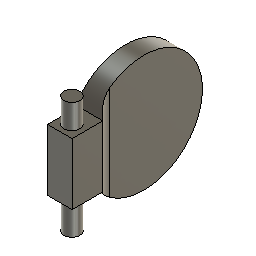
assembly engine1 (Autodesk Fusion 360 archive; units mm, degrees)
design "closing element"
part number: 2026-03-27-16-31-58-847
Autodesk Fusion 360 part; units mm, degrees
sketch "Sketch1" plane through (0, 0, 0) normal (1, 0, 0) x (0, 1, 0)
  circle A0 centre (0, 0) radius 9.5
  dimension "d1" = 19
  constraint coincident A0.centre origin
  measures "d1" diameter of A0
extrude "Extrude1" add sketch "Sketch1" along normal blind 3
sketch "Sketch2" plane through (3, 0, 0) normal (1, 0, 0) x (0, 1, 0)
  circle A0 centre (0, 0) radius 9.5
  line L0 (-8.0777, 5) -> (-13.0777, 5)
  line L1 (-13.0777, 5) -> (-13.0777, -5)
  line L2 (-13.0777, -5) -> (-8.0777, -5)
  line L3 (-8.0777, -5) -> (-8.0777, 5)
  dimension "d4" = 5
  dimension "d5" = 10
  constraint horizontal L0
  constraint vertical L1
  constraint horizontal L2
  constraint vertical L3
  constraint coincident A0 L0.start
  constraint coincident A0 L2.end
  measures "d4" distance of L0.start L0.end
  measures "d5" distance of L0.start L2.end
extrude "Extrude2" add sketch "Sketch2" along normal blind 1 contours A0 L3 | A0 L0 L1 L2 picked at (-8.2821, 1.2788)
extrude "Extrude3" add 1 faces at (3, -11.8852, 0) along direction (-1, 0, 0) blind 2.6
extrude "Extrude4" add 1 faces at (4, -11.4111, 1.6667) along direction (1, 0, 0) blind 0.4
sketch "Sketch3" plane through (0, 0, -5) normal (0, 0, -1) x (1, 0, 0)
  line L0 (3, 8.0777) -> (4.4, 8.0777)
  line L1 (4.4, 8.0777) -> (4.4, 13.0777)
  line L2 (4.4, 13.0777) -> (0.4, 13.0777)
  line L3 (0.4, 13.0777) -> (0.4, 8.0777)
  line L4 (0.4, 8.0777) -> (3, 8.0777)
  line L5 (4.4, 13.0777) -> (0.4, 13.0777)
  line L6 (0.4, 13.0777) -> (0.4, 8.0777)
  line L7 (0.4, 8.0777) -> (4.4, 8.0777)
  line L8 (4.4, 8.0777) -> (4.4, 13.0777)
  circle A0 centre (2.36, 11.0777) radius 1.3
  dimension "d12" = 2.6
  dimension "d21" = 2
  constraint horizontal L5
  constraint vertical L6
  constraint horizontal L7
  constraint vertical L8
  constraint coincident L3.end L4.start
  constraint coincident L1.end L2.start
  measures "d12" diameter of A0
  measures "d21" distance of L5 A0.centre
extrude "Extrude5" add sketch "Sketch3" along normal blind 5 and the other way blind 14 contours A0
fillet "Fillet1" radius 3 1 edges at (3, -8.0777, 0)
fillet "Fillet1" radius 1 1 edges at (0.4, -9.5, 0)

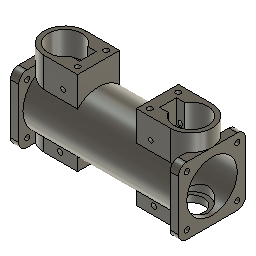
design "hub"
part number: 2026-03-27-13-33-24-088
Autodesk Fusion 360 part; units mm, degrees
sketch "Sketch1" plane through (0, 0, 0) normal (1, 0, 0) x (0, 1, 0)
  circle A0 centre (0, 0) radius 15
  circle A1 centre (0, 0) radius 17.5
  constraint coincident A0.centre A1.centre
  constraint concentric A0 A1
extrude "Extrude1" add sketch "Sketch1" along normal blind 50
extrude "Extrude2" add 1 faces at (0, 6.9889, -15.0815) along direction (-1, 0, 0) blind 50
sketch "Sketch3" plane through (-50, 0, 0) normal (-1, 0, 0) x (0, -1, 0)
  circle A0 centre (0, 0) radius 15
  circle A1 centre (0, 0) radius 17.5
  circle A2 centre (0, 0) radius 15
  line L0 (-15, 20) -> (15, 20)
  line L1 (20, 15) -> (20, -15)
  line L2 (15, -20) -> (-15, -20)
  line L3 (-20, -15) -> (-20, 15)
  line L4 (-20, 20) -> (20, -20) construction
  line L5 (20, 20) -> (-20, -20) construction
  arc A3 (-15, 20) -> (-20, 15) centre (-15, 15) ccw
  arc A4 (20, 15) -> (15, 20) centre (15, 15) ccw
  arc A5 (15, -20) -> (20, -15) centre (15, -15) ccw
  arc A6 (-20, -15) -> (-15, -20) centre (-15, -15) ccw
  circle A7 centre (-15, 15) radius 1.5
  circle A8 centre (15, 15) radius 1.5
  circle A9 centre (15, -15) radius 1.5
  circle A10 centre (-15, -15) radius 1.5
  constraint coincident A0.centre A1.centre
  constraint horizontal L0
  constraint perpendicular L0 L1
  constraint parallel L0 L2
  constraint parallel L1 L3
  constraint coincident L4 A0.centre
  constraint coincident L5 A0.centre
  constraint coincident L4.start L0
  constraint coincident L4.start L3
  constraint tangent L0 A3
  constraint tangent L3 A3
  constraint coincident L5.start L0
  constraint coincident L5.start L1
  constraint tangent L0 A4
  constraint tangent L1 A4
  constraint coincident L4.end L1
  constraint coincident L4.end L2
  constraint tangent L1 A5
  constraint tangent L2 A5
  constraint equal A4 A5
  constraint coincident L5.end L2
  constraint coincident L5.end L3
  constraint tangent L2 A6
  constraint tangent L3 A6
  constraint equal A4 A6
  constraint concentric A3 A7
  constraint concentric A4 A8
  constraint concentric A5 A9
  constraint concentric A6 A10
  constraint equal A7 A8
  constraint equal A8 A10
  constraint equal A9 A10
extrude "Extrude3" add sketch "Sketch3" against normal blind 5 contours L0 L1 L2 L3 A3 A4 A5 A6
mirror "Mirror1" about plane through (0, 0, 0) normal (1, 0, 0) of "Extrude3"
sketch "Sketch4" plane through (0, 0, 0) normal (0, 0, 1) x (1, 0, 0)
  circle A0 centre (-37.5, 0) radius 12.5
  line L0 (-50, 15) -> (-50, -15)
  circle A1 centre (-37.5, 0) radius 10
  constraint tangent A0 L0
  constraint concentric A0 A1
extrude "Extrude4" add sketch "Sketch4" along normal up to surface (20 mm away) contours A0 | A1
sketch "Sketch5" plane through (0, 0, 20) normal (0, 0, 1) x (-1, 0, 0)
  line L0 (45, -10) -> (45, -15)
  line L1 (45, -15) -> (50, -15)
  line L2 (50, -15) -> (50, 15)
  line L3 (50, 15) -> (45, 15)
  line L4 (45, 15) -> (45, 10)
  arc A0 (45, 10) -> (45, -10) centre (37.5, 0) ccw
  circle A1 centre (37.5, 0) radius 10
  constraint concentric A0 A1
extrude "Extrude5" cut sketch "Sketch5" against normal blind 5 contours A1
sketch "Sketch6" plane through (0, 0, 20) normal (0, 0, 1) x (-1, 0, 0)
  circle A0 centre (37.5, 0) radius 10
  line L0 (45, -10) -> (45, -15)
  line L1 (45, -15) -> (50, -15)
  line L2 (50, -15) -> (50, 15)
  line L3 (50, 15) -> (45, 15)
  line L4 (45, 15) -> (45, 10)
  arc A1 (45, 10) -> (45, -10) centre (37.5, 0) ccw
  arc A2 (45, 10) -> (45, -10) centre (37.5, 0) ccw
  line L5 (37.5, -12.5) -> (17.5, -12.5)
  line L6 (37.5, 12.5) -> (17.5, 12.5)
  line L7 (17.5, -12.5) -> (17.5, 12.5)
  constraint coincident A2 L5.start
  constraint horizontal L5
  constraint tangent A1 L5
  constraint coincident A1 L6.start
  constraint parallel L5 L6
  constraint tangent A2 L6
  constraint perpendicular L6 L7
extrude "Extrude6" add sketch "Sketch6" along normal up to surface contours A1 A2 L5 L6 L7 end surface at (15, -15.1577, 8.7461)
sketch "Sketch7" plane through (0, 0, 20) normal (0, 0, 1) x (-1, 0, 0)
  circle A0 centre (37.5, 0) radius 10
  line L0 (45, -10) -> (45, -15)
  line L1 (45, -15) -> (50, -15)
  line L2 (50, -15) -> (50, 15)
  line L3 (50, 15) -> (45, 15)
  line L4 (45, 15) -> (45, 10)
  arc A1 (45, 10) -> (37.5, 12.5) centre (37.5, 0) ccw
  line L5 (37.5, 12.5) -> (17.5, 12.5)
  line L6 (17.5, 12.5) -> (17.5, -12.5)
  line L7 (17.5, -12.5) -> (37.5, -12.5)
  arc A2 (37.5, -12.5) -> (45, -10) centre (37.5, 0) ccw
  line L8 (28.8397, -5) -> (23.8397, -5)
  line L9 (23.8397, -5) -> (23.8397, 5)
  line L10 (23.8397, 5) -> (28.8397, 5)
  line L11 (28.8397, 5) -> (28.8397, -5)
  constraint horizontal L8
  constraint vertical L9
  constraint horizontal L10
  constraint vertical L11
  constraint coincident A0 L8.start
extrude "Extrude7" cut sketch "Sketch7" against normal up to surface (5 mm away) contours A0 L8 L9 L10
sketch "Sketch8" plane through (-50, 0, 0) normal (-1, 0, 0) x (0, -1, 0)
  line L0 (15, 20) -> (-15, 20)
  arc A0 (-15, 20) -> (-20, 15) centre (-15, 15) ccw
  line L1 (-20, 15) -> (-20, -15)
  arc A1 (-20, -15) -> (-15, -20) centre (-15, -15) ccw
  line L2 (-15, -20) -> (15, -20)
  arc A2 (15, -20) -> (20, -15) centre (15, -15) ccw
  line L3 (20, -15) -> (20, 15)
  arc A3 (20, 15) -> (15, 20) centre (15, 15) ccw
  circle A4 centre (0, 0) radius 15
  circle A5 centre (-15, 15) radius 1.5
  circle A6 centre (-15, -15) radius 1.5
  circle A7 centre (15, 15) radius 1.5
  circle A8 centre (15, -15) radius 1.5
extrude "Extrude8" cut sketch "Sketch8" against normal blind 101 contours A4
sketch "Sketch9" plane through (0, 0, 20) normal (0, 0, 1) x (-1, 0, 0)
  line L0 (45, -10) -> (45, -15)
  line L1 (45, -15) -> (50, -15)
  line L2 (50, -15) -> (50, 15)
  line L3 (50, 15) -> (45, 15)
  line L4 (45, 15) -> (45, 10)
  arc A0 (45, 10) -> (37.5, 12.5) centre (37.5, 0) ccw
  line L5 (37.5, 12.5) -> (17.5, 12.5)
  line L6 (17.5, 12.5) -> (17.5, -12.5)
  line L7 (17.5, -12.5) -> (37.5, -12.5)
  arc A1 (37.5, -12.5) -> (45, -10) centre (37.5, 0) ccw
  line L8 (28.8397, -5) -> (23.8397, -5)
  line L9 (23.8397, -5) -> (23.8397, 5)
  line L10 (23.8397, 5) -> (28.8397, 5)
  arc A2 (28.8397, -5) -> (28.8397, 5) centre (37.5, 0) ccw
  circle A3 centre (37.5, 0) radius 7.433
  constraint concentric A0 A3
extrude "Extrude9" cut sketch "Sketch9" against normal blind 8 contours A3
extrude "Extrude10" add 1 faces at (-25.8932, 3.3333, 15) along direction (0, 0, 1) blind 1
extrude "Extrude11" add 1 faces at (-25.5064, -3.3333, 15) along direction (0, 0, 1) blind 1
sketch "Sketch10" plane through (0, 5, 0) normal (0, -1, 0) x (1, 0, 0)
  line L0 (-28.8397, 16) -> (-23.8397, 16)
  line L1 (-23.8397, 16) -> (-23.8397, 20)
  line L2 (-23.8397, 20) -> (-28.8397, 20)
  line L3 (-28.8397, 20) -> (-28.8397, 16)
  line L4 (-28.8397, 20) -> (-23.3767, 20)
  line L5 (-23.3767, 20) -> (-23.3767, 16)
  line L6 (-23.3767, 16) -> (-28.8397, 16)
  line L7 (-28.8397, 16) -> (-28.8397, 20)
  line L8 (-28.8397, 20) -> (-23.3767, 16) construction
  line L9 (-23.3767, 20) -> (-28.8397, 16) construction
  circle A0 centre (-26.1082, 18) radius 1.3481
  point P0 (-26.1082, 18)
  constraint horizontal L4
  constraint perpendicular L4 L5
  constraint parallel L4 L6
  constraint parallel L5 L7
  constraint coincident L8 P0
  constraint coincident L9 P0
  constraint coincident L2.end L3.start
  constraint coincident L0 L3.end
  constraint coincident P0 A0.centre
extrude "Extrude12" cut sketch "Sketch10" along normal blind 18 and the other way blind 8 contours A0
mirror "Mirror2" about plane through (0, 0, 0) normal (1, 0, 0) of "Extrude4", "Extrude5", "Extrude6", "Extrude7", "Extrude8", "Extrude9", "Extrude10", "Extrude11", "Extrude12"
sketch "Sketch11" plane through (0, 0, 0) normal (0, 0, 1) x (1, 0, 0)
  line L0 (-50, -15) -> (-50, 15)
  line L1 (-37.5, -12.5) -> (-17.5, -12.5)
  line L2 (-17.5, -12.5) -> (-17.5, 12.5)
  line L3 (-17.5, 12.5) -> (-37.5, 12.5)
  arc A0 (-37.5, 12.5) -> (-37.5, -12.5) centre (-37.5, 0) ccw
  line L4 (-28.8397, -5) -> (-23.8397, -5)
  line L5 (-23.8397, -5) -> (-23.8397, 5)
  line L6 (-23.8397, 5) -> (-28.8397, 5)
  arc A1 (-28.8397, 5) -> (-28.8397, -5) centre (-37.5, 0) ccw
  constraint tangent L0 A0
  constraint concentric A0 A1
  constraint horizontal L1
  constraint vertical L2
  constraint horizontal L3
  constraint tangent L1 A0
  constraint tangent L3 A0
  constraint horizontal L4
  constraint vertical L5
  constraint horizontal L6
extrude "Extrude13" add sketch "Sketch11" against normal up to surface (20 mm away)
sketch "Sketch12" plane through (-50, 0, 0) normal (-1, 0, 0) x (0, -1, 0)
  line L0 (-15, -20) -> (15, -20)
  arc A0 (15, -20) -> (20, -15) centre (15, -15) ccw
  line L1 (20, -15) -> (20, 15)
  arc A1 (20, 15) -> (15, 20) centre (15, 15) ccw
  line L2 (15, 20) -> (-15, 20)
  arc A2 (-15, 20) -> (-20, 15) centre (-15, 15) ccw
  line L3 (-20, 15) -> (-20, -15)
  arc A3 (-20, -15) -> (-15, -20) centre (-15, -15) ccw
  circle A4 centre (0, 0) radius 15
  circle A5 centre (-15, 15) radius 1.5
  circle A6 centre (-15, -15) radius 1.5
  circle A7 centre (15, 15) radius 1.5
  circle A8 centre (15, -15) radius 1.5
extrude "Extrude14" cut sketch "Sketch12" against normal blind 103 contours A4
sketch "Sketch13" plane through (0, 0, -20) normal (0, 0, -1) x (1, 0, 0)
  line L0 (-45, 10) -> (-45, 15)
  line L1 (-45, 15) -> (-50, 15)
  line L2 (-50, 15) -> (-50, -15)
  line L3 (-50, -15) -> (-45, -15)
  line L4 (-45, -15) -> (-45, -10)
  arc A0 (-45, -10) -> (-37.5, -12.5) centre (-37.5, 0) ccw
  line L5 (-37.5, -12.5) -> (-17.5, -12.5)
  line L6 (-17.5, -12.5) -> (-17.5, 12.5)
  line L7 (-17.5, 12.5) -> (-37.5, 12.5)
  arc A1 (-37.5, 12.5) -> (-45, 10) centre (-37.5, 0) ccw
  arc A2 (-28.8397, 5) -> (-45, 6.6144) centre (-37.5, 0) ccw
  line L8 (-28.8397, 5) -> (-23.8397, 5)
  line L9 (-23.8397, 5) -> (-23.8397, -5)
  line L10 (-23.8397, -5) -> (-28.8397, -5)
  arc A3 (-45, -6.6144) -> (-28.8397, -5) centre (-37.5, 0) ccw
  line L11 (-45, -6.6144) -> (-45, 6.6144)
  circle A4 centre (-37.5, 0) radius 10
  constraint concentric A0 A4
extrude "Extrude15" cut sketch "Sketch13" against normal blind 7 contours A2 A3 L11 A4 | L11 A4
sketch "Sketch14" plane through (0, 0, -20) normal (0, 0, -1) x (1, 0, 0)
  arc A0 (-28.8397, 5) -> (-28.8397, -5) centre (-37.5, 0) ccw
  line L0 (-28.8397, 5) -> (-23.8397, 5)
  line L1 (-23.8397, 5) -> (-23.8397, -5)
  line L2 (-23.8397, -5) -> (-28.8397, -5)
  line L3 (-45, 10) -> (-45, 15)
  line L4 (-45, 15) -> (-50, 15)
  line L5 (-50, 15) -> (-50, -15)
  line L6 (-50, -15) -> (-45, -15)
  line L7 (-45, -15) -> (-45, -10)
  arc A1 (-45, -10) -> (-37.5, -12.5) centre (-37.5, 0) ccw
  line L8 (-37.5, -12.5) -> (-17.5, -12.5)
  line L9 (-17.5, -12.5) -> (-17.5, 12.5)
  line L10 (-17.5, 12.5) -> (-37.5, 12.5)
  arc A2 (-37.5, 12.5) -> (-45, 10) centre (-37.5, 0) ccw
  line L11 (-28.8397, 5) -> (-26.8397, 5)
  line L12 (-26.8397, 5) -> (-26.8397, -5)
  line L13 (-26.8397, -5) -> (-28.8397, -5)
  line L14 (-28.8397, -5) -> (-28.8397, 5)
  constraint horizontal L11
  constraint vertical L12
  constraint horizontal L13
  constraint vertical L14
  constraint coincident L2 L12.end
  constraint coincident A0.start L0.start
extrude "Extrude16" cut sketch "Sketch14" against normal blind 9 contours L0 L2 L11 L12 L13 L14
sketch "Sketch15" plane through (0, 0, -20) normal (0, 0, -1) x (1, 0, 0)
  arc A0 (-28.8397, 5) -> (-28.8397, -5) centre (-37.5, 0) ccw
  line L0 (-28.8397, 5) -> (-23.8397, 5)
  line L1 (-23.8397, 5) -> (-23.8397, -5)
  line L2 (-23.8397, -5) -> (-28.8397, -5)
  line L3 (-45, 10) -> (-45, 15)
  line L4 (-45, 15) -> (-50, 15)
  line L5 (-50, 15) -> (-50, -15)
  line L6 (-50, -15) -> (-45, -15)
  line L7 (-45, -15) -> (-45, -10)
  arc A1 (-45, -10) -> (-37.5, -12.5) centre (-37.5, 0) ccw
  line L8 (-37.5, -12.5) -> (-17.5, -12.5)
  line L9 (-17.5, -12.5) -> (-17.5, 12.5)
  line L10 (-17.5, 12.5) -> (-37.5, 12.5)
  arc A2 (-37.5, 12.5) -> (-45, 10) centre (-37.5, 0) ccw
  circle A3 centre (-37.5, 0) radius 7.5
  arc A4 (-28.8397, 5) -> (-28.8397, -5) centre (-37.5, 0) ccw
  line L11 (-23.8397, 5) -> (-28.8397, 5)
  line L12 (-23.8397, -5) -> (-23.8397, 5)
  line L13 (-28.8397, -5) -> (-23.8397, -5)
  constraint concentric A0 A3
extrude "Extrude17" add sketch "Sketch15" against normal blind 4 contours A0 L0 L1 L2 A4 L11 L12 L13
extrude "Extrude18" cut 2 faces at (-39.0496, 7.9401, -13) (-38.298, -8.2253, -13) along direction (0, 0, 1) blind 4
sketch "Sketch16" plane through (0, 5, 0) normal (0, -1, 0) x (1, 0, 0)
  line L0 (-28.8397, -16) -> (-26.8397, -16)
  line L1 (-26.8397, -16) -> (-26.8397, -14.1421)
  line L2 (-26.8397, -14.1421) -> (-28.8397, -14.1421)
  line L3 (-28.8397, -14.1421) -> (-28.8397, -16)
  line L4 (-28.8397, -14.1421) -> (-26.8397, -14.1421)
  line L5 (-26.8397, -14.1421) -> (-26.8397, -16)
  line L6 (-26.8397, -16) -> (-28.8397, -16)
  line L7 (-28.8397, -16) -> (-28.8397, -14.1421)
  line L8 (-28.8397, -14.1421) -> (-26.8397, -16) construction
  line L9 (-26.8397, -14.1421) -> (-28.8397, -16) construction
  circle A0 centre (-27.8397, -15.0711) radius 1.5
  point P0 (-27.8397, -15.0711)
  constraint horizontal L4
  constraint perpendicular L4 L5
  constraint parallel L4 L6
  constraint parallel L5 L7
  constraint coincident L8 P0
  constraint coincident L9 P0
  constraint coincident L2.end L3.start
  constraint coincident P0 A0.centre
extrude "Extrude19" cut sketch "Sketch16" along normal blind 20 and the other way blind 25 contours L0 L1 L2 L3 L4 L5 L6 L7 | A0
mirror "Mirror3" about plane through (0, 0, 0) normal (1, 0, 0) of "Extrude13", "Extrude14", "Extrude15", "Extrude16", "Extrude17", "Extrude18", "Extrude19"
sketch "Sketch17" plane through (-50, 0, 0) normal (-1, 0, 0) x (0, -1, 0)
  line L0 (-15, -20) -> (15, -20)
  arc A0 (15, -20) -> (20, -15) centre (15, -15) ccw
  line L1 (20, -15) -> (20, 15)
  arc A1 (20, 15) -> (15, 20) centre (15, 15) ccw
  line L2 (15, 20) -> (-15, 20)
  arc A2 (-15, 20) -> (-20, 15) centre (-15, 15) ccw
  line L3 (-20, 15) -> (-20, -15)
  arc A3 (-20, -15) -> (-15, -20) centre (-15, -15) ccw
  circle A4 centre (0, 0) radius 15
  circle A5 centre (-15, 15) radius 1.5
  circle A6 centre (-15, -15) radius 1.5
  circle A7 centre (15, 15) radius 1.5
  circle A8 centre (15, -15) radius 1.5
  circle A9 centre (0, 0) radius 15
  constraint coincident A4.centre A9.centre
extrude "Extrude20" add sketch "Sketch17" against normal blind 2 contours A4 A9
sketch "Sketch18" plane through (0, 0, 20) normal (0, 0, 1) x (-1, 0, 0)
  line L0 (-45, 10) -> (-45, 15)
  line L1 (-45, 15) -> (-50, 15)
  line L2 (-50, 15) -> (-50, -15)
  line L3 (-50, -15) -> (-45, -15)
  line L4 (-45, -15) -> (-45, -10)
  arc A0 (-45, -10) -> (-37.5, -12.5) centre (-37.5, 0) ccw
  line L5 (-37.5, -12.5) -> (-17.5, -12.5)
  line L6 (-17.5, -12.5) -> (-17.5, 12.5)
  line L7 (-17.5, 12.5) -> (-37.5, 12.5)
  arc A1 (-37.5, 12.5) -> (-45, 10) centre (-37.5, 0) ccw
  line L8 (-28.8397, 5) -> (-23.8397, 5)
  line L9 (-23.8397, 5) -> (-23.8397, -5)
  line L10 (-23.8397, -5) -> (-28.8397, -5)
  arc A2 (-28.8397, 5) -> (-28.8397, -5) centre (-37.5, 0) ccw
  circle A3 centre (-37.5, 0) radius 7.433
  line L11 (-23.8397, -5) -> (-23.8397, 5)
  line L12 (-23.8397, 5) -> (-28.8397, 5)
  arc A4 (-28.8397, 5) -> (-28.8397, -5) centre (-37.5, 0) ccw
  line L13 (-28.8397, -5) -> (-23.8397, -5)
  line L14 (23.8397, 5) -> (23.8397, -5)
  line L15 (23.8397, -5) -> (28.8397, -5)
  arc A5 (28.8397, -5) -> (28.8397, 5) centre (37.5, 0) ccw
  line L16 (28.8397, 5) -> (23.8397, 5)
  circle A6 centre (37.5, 0) radius 7.433
  line L17 (45, -10) -> (45, -15)
  line L18 (45, -15) -> (50, -15)
  line L19 (50, -15) -> (50, 15)
  line L20 (50, 15) -> (45, 15)
  line L21 (45, 15) -> (45, 10)
  arc A7 (45, 10) -> (37.5, 12.5) centre (37.5, 0) ccw
  line L22 (37.5, 12.5) -> (17.5, 12.5)
  line L23 (17.5, 12.5) -> (17.5, -12.5)
  line L24 (17.5, -12.5) -> (37.5, -12.5)
  arc A8 (37.5, -12.5) -> (45, -10) centre (37.5, 0) ccw
  line L25 (28.8397, -5) -> (23.8397, -5)
  line L26 (23.8397, -5) -> (23.8397, 5)
  line L27 (23.8397, 5) -> (28.8397, 5)
  arc A9 (28.8397, -5) -> (28.8397, 5) centre (37.5, 0) ccw
  circle A10 centre (37.5, 0) radius 12.5
  circle A11 centre (-37.5, 0) radius 10
  circle A12 centre (-37.5, 0) radius 12.5
  constraint concentric A5 A10
  constraint coincident L17.start A10
  constraint concentric A3 A11
  constraint concentric A3 A12
  constraint coincident L0.start A12
extrude "Extrude21" add sketch "Sketch18" along normal blind 10 contours A0 A1 L8 L10 A2 L12 A4 L13 A11 A12 | L5 L6 L7 L8 L9 L10 L11 L12 L13 A12 | L14 L15 L16 L22 L23 L24 L25 L26 L27 A10 | L15 A5 L16 A7 A8 L25 L27 A9 A10
sketch "Sketch19" plane through (0, 0, 30) normal (0, 0, 1) x (-1, 0, 0)
  line L0 (28.8397, -5) -> (23.8397, -5)
  line L1 (23.8397, -5) -> (23.8397, 5)
  line L2 (23.8397, 5) -> (28.8397, 5)
  arc A0 (28.8397, -5) -> (28.8397, 5) centre (37.5, 0) ccw
  arc A1 (37.5, -12.5) -> (37.5, 12.5) centre (37.5, 0) ccw
  line L3 (37.5, 12.5) -> (17.5, 12.5)
  line L4 (17.5, 12.5) -> (17.5, -12.5)
  line L5 (17.5, -12.5) -> (37.5, -12.5)
  line L6 (-28.8397, 5) -> (-23.8397, 5)
  line L7 (-23.8397, 5) -> (-23.8397, -5)
  line L8 (-23.8397, -5) -> (-28.8397, -5)
  arc A2 (-28.8397, 5) -> (-28.8397, -5) centre (-37.5, 0) ccw
  line L9 (-17.5, 12.5) -> (-37.5, 12.5)
  arc A3 (-37.5, 12.5) -> (-37.5, -12.5) centre (-37.5, 0) ccw
  line L10 (-37.5, -12.5) -> (-17.5, -12.5)
  line L11 (-17.5, -12.5) -> (-17.5, 12.5)
  arc A4 (37.5, -8.5) -> (37.5, 8.5) centre (37.5, 0) ccw
  line L12 (37.5, 8.5) -> (21.5, 8.5)
  line L13 (21.5, 8.5) -> (21.5, -8.5)
  line L14 (21.5, -8.5) -> (37.5, -8.5)
  line L15 (-21.5, 8.5) -> (-37.5, 8.5)
  arc A5 (-37.5, 8.5) -> (-37.5, -8.5) centre (-37.5, 0) ccw
  line L16 (-37.5, -8.5) -> (-21.5, -8.5)
  line L17 (-21.5, -8.5) -> (-21.5, 8.5)
  circle A6 centre (21.5, -8.5) radius 1.5
  circle A7 centre (21.5, 8.5) radius 1.5
  circle A8 centre (-21.5, -8.5) radius 1.5
  circle A9 centre (-21.5, 8.5) radius 1.5
  constraint coincident L13.end L14.start
  constraint coincident L12.end L13.start
  constraint coincident L16.end L17.start
  constraint coincident L15.start L17.end
  constraint equal A6 A8
  constraint equal A8 A9
  constraint equal A7 A9
extrude "Extrude22" cut sketch "Sketch19" against normal blind 5 contours L13 L14 A6 | L13 L14 A6 | L12 L13 A7 | L12 L13 A7 | L15 L17 A9 | L15 L17 A9 | L16 L17 A8 | L16 L17 A8
sketch "Sketch20" plane through (0, 0, -20) normal (0, 0, -1) x (1, 0, 0)
  circle A0 centre (37.5, 0) radius 7.5
  line L0 (45, -10) -> (45, -15)
  line L1 (45, -15) -> (50, -15)
  line L2 (50, -15) -> (50, 15)
  line L3 (50, 15) -> (45, 15)
  line L4 (45, 15) -> (45, 10)
  arc A1 (45, 10) -> (37.5, 12.5) centre (37.5, 0) ccw
  line L5 (37.5, 12.5) -> (17.5, 12.5)
  line L6 (17.5, 12.5) -> (17.5, -12.5)
  line L7 (17.5, -12.5) -> (37.5, -12.5)
  arc A2 (37.5, -12.5) -> (45, -10) centre (37.5, 0) ccw
  circle A3 centre (-37.5, 0) radius 7.5
  line L8 (-45, 10) -> (-45, 15)
  line L9 (-45, 15) -> (-50, 15)
  line L10 (-50, 15) -> (-50, -15)
  line L11 (-50, -15) -> (-45, -15)
  line L12 (-45, -15) -> (-45, -10)
  arc A4 (-45, -10) -> (-37.5, -12.5) centre (-37.5, 0) ccw
  line L13 (-37.5, -12.5) -> (-17.5, -12.5)
  line L14 (-17.5, -12.5) -> (-17.5, 12.5)
  line L15 (-17.5, 12.5) -> (-37.5, 12.5)
  arc A5 (-37.5, 12.5) -> (-45, 10) centre (-37.5, 0) ccw
  arc A6 (37.5, -8.5) -> (42.6, -6.8) centre (37.5, 0) ccw
  arc A7 (46, -6.127) -> (42.6, -6.8) centre (45, -10) ccw
  line L16 (46, -6.127) -> (46, 6.127)
  arc A8 (42.6, 6.8) -> (46, 6.127) centre (45, 10) ccw
  arc A9 (42.6, 6.8) -> (37.5, 8.5) centre (37.5, 0) ccw
  line L17 (37.5, 8.5) -> (21.5, 8.5)
  line L18 (21.5, 8.5) -> (21.5, -8.5)
  line L19 (21.5, -8.5) -> (37.5, -8.5)
  arc A10 (-37.5, 8.5) -> (-42.6, 6.8) centre (-37.5, 0) ccw
  arc A11 (-46, 6.127) -> (-42.6, 6.8) centre (-45, 10) ccw
  line L20 (-46, 6.127) -> (-46, -6.127)
  arc A12 (-42.6, -6.8) -> (-46, -6.127) centre (-45, -10) ccw
  arc A13 (-42.6, -6.8) -> (-37.5, -8.5) centre (-37.5, 0) ccw
  line L21 (-37.5, -8.5) -> (-21.5, -8.5)
  line L22 (-21.5, -8.5) -> (-21.5, 8.5)
  line L23 (-21.5, 8.5) -> (-37.5, 8.5)
  circle A14 centre (21.5, -8.5) radius 1.5
  circle A15 centre (21.5, 8.5) radius 1.5
  circle A16 centre (-21.5, -8.5) radius 1.5
  circle A17 centre (-21.5, 8.5) radius 1.5
  constraint coincident L18.end L19.start
  constraint coincident L17.end L18.start
  constraint coincident L21.end L22.start
  constraint coincident L22.end L23.start
  constraint equal A14 A15
  constraint equal A15 A17
  constraint equal A16 A17
extrude "Extrude23" cut sketch "Sketch20" against normal blind 5 contours L18 L19 A14 | L18 L19 A14 | L17 L18 A15 | L17 L18 A15 | L22 L23 A17 | L22 L23 A17 | L21 L22 A16 | L21 L22 A16

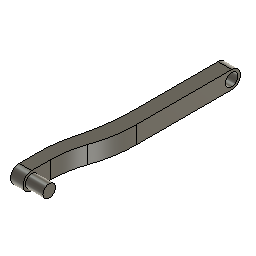
design "connecting rod"
part number: 2026-03-27-15-36-50-826
Autodesk Fusion 360 part; units mm, degrees
sketch "Sketch1" plane through (0, 0, 0) normal (1, 0, 0) x (0, 1, 0)
  circle A0 centre (0, 0) radius 2.5
  dimension "d1" = 5
  constraint coincident A0.centre origin
  measures "d1" diameter of A0
extrude "Extrude1" add sketch "Sketch1" along normal blind 7
sketch "Sketch2" plane through (0, 0, 0) normal (-1, 0, 0) x (0, -1, 0)
  circle A0 centre (0, 0) radius 2.5
  circle A1 centre (0, 0) radius 3.5
  dimension "d4" = 7
  constraint coincident A0.centre A1.centre
  measures "d4" diameter of A1
extrude "Extrude2" add sketch "Sketch2" along normal blind 5 contours A0 | A1
sketch "Sketch3" plane through (-5, 0, 0) normal (-1, 0, 0) x (0, -1, 0)
  circle A0 centre (0, 0) radius 3.5
  circle A1 centre (0, 0) radius 3.5
  line L0 (0, 3.5) -> (-75, 3.5)
  line L1 (-78.5, 0) -> (-78.5, -3.5) construction
  line L2 (-78.5, -3.5) -> (0, -3.5)
  line L3 (0, -3.5) -> (0, 3.5)
  arc A2 (-75, 3.5) -> (-75, -3.5) centre (-75, 0) ccw
  dimension "d7" = 75
  constraint horizontal L0
  constraint vertical L1
  constraint horizontal L2
  constraint vertical L3
  constraint coincident A1 L0.start
  constraint coincident A1 L2.end
  constraint tangent A0 L0
  constraint tangent L0 A2
  constraint tangent L2 A2
  constraint tangent L1 A2
  constraint coincident L1.start A2
  constraint coincident L2 A2.end
  constraint coincident L0 A2.start
  constraint coincident L0.end A2.start
  measures "d7" distance of L0.start L0.end
extrude "Extrude3" add sketch "Sketch3" against normal up to surface (5 mm away) contours A0 A1 L0 L2 A2
sketch "Sketch4" plane through (0, 0, 0) normal (1, 0, 0) x (0, 1, 0)
  line L0 (0, -3.5) -> (75, -3.5)
  arc A0 (75, -3.5) -> (75, 3.5) centre (75, 0) ccw
  line L1 (75, 3.5) -> (0, 3.5)
  arc A1 (0, 3.5) -> (0, -3.5) centre (0, 0) ccw
  circle A2 centre (0, 0) radius 2.5
  circle A3 centre (75, 0) radius 2.5
  dimension "d10" = 5
  constraint concentric A0 A3
  measures "d10" diameter of A3
extrude "Extrude4" add sketch "Sketch4" along normal up to surface (7 mm away) contours A3
extrude "Extrude5" cut 1 faces at (7, 75.3045, -1.0241) along direction (-1, 0, 0) blind 33
sketch "Sketch5" plane through (-5, 0, 0) normal (-1, 0, 0) x (0, -1, 0)
  circle A0 centre (-75, 0) radius 2.5
  arc A1 (0, -3.5) -> (0, 3.5) centre (0, 0) ccw
  line L0 (0, 3.5) -> (-75, 3.5)
  arc A2 (-75, 3.5) -> (-75, -3.5) centre (-75, 0) ccw
  line L1 (-75, -3.5) -> (0, -3.5)
  line L2 (-15, -3.5) -> (-15, 3.5)
  dimension "d15" = 15
  constraint coincident L1 L2.start
  constraint coincident L0 L2.end
  constraint perpendicular L0 L2
  measures "d15" distance of A1.centre L2
extrude "Extrude6" add sketch "Sketch5" against normal blind 10 contours L0 A2 L1 L2
sketch "Sketch6" plane through (5, 0, 0) normal (1, 0, 0) x (0, 1, 0)
  circle A0 centre (75, 0) radius 2.5
  line L0 (15, 3.5) -> (15, -3.5)
  line L1 (15, -3.5) -> (75, -3.5)
  arc A1 (75, -3.5) -> (75, 3.5) centre (75, 0) ccw
  line L2 (75, 3.5) -> (15, 3.5)
extrude "Extrude7" cut sketch "Sketch6" against normal blind 8 from surface at -5.5
fillet "Fillet1" radius 84 1 edges at (-0.5, 15, 0)
fillet "Fillet2" radius 50.5 1 edges at (5, 15, 0)
fillet "Fillet3" radius 48.5 1 edges at (-5, 15, 0)
fillet "Fillet3" radius 38.5 1 edges at (0, 15, 0)

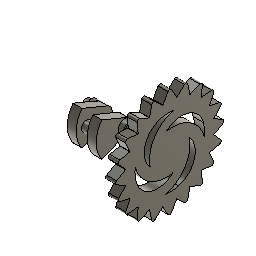
design "shaft"
part number: 2026-03-27-15-48-30-231
Autodesk Fusion 360 part; units mm, degrees
sketch "Sketch1" plane through (0, 0, 0) normal (1, 0, 0) x (0, 1, 0)
  circle A0 centre (0, 0) radius 2.5 construction
  circle A1 centre (0, 0) radius 14.5
  circle A2 centre (0, 0) radius 9.5 construction
  circle A3 centre (-9.4991, -0.128) radius 2.5
  circle A4 centre (0, 0) radius 3.5
  line L0 (1.3394, 3.2336) -> (-11.6607, 8.6184)
  line L1 (1.3394, -3.2336) -> (-11.6607, -8.6184)
  line L2 (0, 0) -> (-7.0024, 0) construction
  dimension "d1" = 29
  dimension "d2" = 5
  dimension "d3" = 5
  dimension "d4" = 5
  dimension "d5" = 7
  dimension "d6" = 45
  dimension "d7" = 22.5
  constraint coincident A0.centre A1.centre
  constraint coincident A2 A3.centre
  constraint concentric A2 A4
  constraint coincident A4 L0.start
  constraint coincident A1 L0.end
  constraint coincident A4 L1.start
  constraint coincident A1 L1.end
  constraint tangent A4 L0
  constraint tangent A4 L1
  constraint coincident A3 L2.end
  constraint horizontal L2
  measures "d1" diameter of A1
  measures "d2" diameter of A0
  measures "d3" distance of A1 A2
  measures "d4" diameter of A3
  measures "d5" diameter of A4
  measures "d6" angle of L0 L1
  measures "d7" angle of L1 L2
extrude "Extrude1" add sketch "Sketch1" along normal blind 4.5 contours A1 A4 L0 L1 | A4 picked at (-7.3196, 4.4977)
sketch "Sketch2" plane through (0, 0, 0) normal (-1, 0, 0) x (0, -1, 0)
  circle A0 centre (9.4991, -0.128) radius 2.5
  line L0 (11.6607, 8.6184) -> (-1.3394, 3.2336)
  arc A1 (-1.3394, 3.2336) -> (-1.3394, -3.2336) centre (0, 0) ccw
  line L1 (-1.3394, -3.2336) -> (11.6607, -8.6184)
  arc A2 (11.6607, -8.6184) -> (11.6607, 8.6184) centre (0, 0) ccw
extrude "Extrude2" add sketch "Sketch2" against normal blind 10 contours A0
sketch "Sketch3" plane through (10, 0, 0) normal (1, 0, 0) x (0, 1, 0)
  circle A0 centre (-9.4991, -0.128) radius 2.5
  line L0 (1.3394, 3.2336) -> (-11.6607, 8.6184)
  circle A1 centre (-9.4991, -0.128) radius 2.5
  line L1 (1.3394, 3.2336) -> (-11.6607, 8.6184)
  arc A2 (-11.6607, 8.6184) -> (-11.6607, -8.6184) centre (0, 0) ccw
  line L2 (-11.6607, -8.6184) -> (1.3394, -3.2336)
  arc A3 (1.3394, -3.2336) -> (1.3394, 3.2336) centre (0, 0) ccw
extrude "Extrude3" add sketch "Sketch3" along normal blind 4.5 contours A0 A1 | L0 L1 A2 L2 A3
sketch "Sketch4" plane through (14.5, 0, 0) normal (1, 0, 0) x (0, 1, 0)
  arc A0 (1.3394, -3.2336) -> (1.3394, 3.2336) centre (0, 0) ccw
  line L0 (1.3394, 3.2336) -> (-11.6607, 8.6184)
  arc A1 (-11.6607, 8.6184) -> (-11.6607, -8.6184) centre (0, 0) ccw
  line L1 (-11.6607, -8.6184) -> (1.3394, -3.2336)
  circle A2 centre (0, 0) radius 3.5
  dimension "d14" = 7
  constraint coincident A0.centre A1.centre
  measures "d14" diameter of A2
extrude "Extrude4" add sketch "Sketch4" along normal blind 2.5 contours A0 A2
sketch "Sketch5" plane through (17, 0, 0) normal (1, 0, 0) x (0, 1, 0)
  circle A0 centre (0, 0) radius 3.5
  circle A1 centre (0, 0) radius 2.5
  dimension "d17" = 5
  constraint concentric A0 A1
  measures "d17" diameter of A1
extrude "Extrude5" add sketch "Sketch5" along normal blind 15 contours A1
sketch "Sketch6" plane through (0, 0, 0) normal (-1, 0, 0) x (0, -1, 0)
  line L0 (11.6607, 8.6184) -> (-1.3394, 3.2336)
  arc A0 (-1.3394, 3.2336) -> (-1.3394, -3.2336) centre (0, 0) ccw
  line L1 (-1.3394, -3.2336) -> (11.6607, -8.6184)
  arc A1 (11.6607, -8.6184) -> (11.6607, 8.6184) centre (0, 0) ccw
  circle A2 centre (0, 0) radius 3.5
  constraint coincident A0.centre A1.centre
extrude "Extrude6" add sketch "Sketch6" along normal blind 2.5 contours A0 A2
sketch "Sketch7" plane through (-2.5, 0, 0) normal (-1, 0, 0) x (0, -1, 0)
  circle A0 centre (0, 0) radius 3.5
  circle A1 centre (0, 0) radius 2.5
  dimension "d22" = 5
  constraint concentric A0 A1
  measures "d22" diameter of A1
extrude "Extrude7" add sketch "Sketch7" along normal blind 2.5 contours A1
sketch "Sketch8" plane through (32, 0, 0) normal (1, 0, 0) x (0, 1, 0)
  circle A0 centre (0, 0) radius 2.5
  circle A1 centre (0, 0) radius 2.5
  circle A2 centre (0, 0) radius 22.5
  dimension "d25" = 20
  dimension "d26" = 5
  constraint concentric A0 A1
  constraint concentric A1 A2
  measures "d25" distance of A1 A2
  measures "d26" diameter of A1
extrude "Extrude8" add sketch "Sketch8" along normal blind 5 contours A0 A1 | A2
sketch "Sketch9" plane through (37, 0, 0) normal (1, 0, 0) x (0, 1, 0)
  circle A0 centre (0, 0) radius 22.5
  line L0 (-3.4641, -22.2317) -> (0, -28.2317)
  line L1 (0, -28.2317) -> (3.4641, -22.2317)
  line L2 (3.4641, -22.2317) -> (-3.4641, -22.2317)
  point P0 (0, -24.2317)
  dimension "d29" = 2
  constraint coincident A0 L1.end
  constraint horizontal L2
  constraint coincident A0 L0.start
  measures "d29" distance of P0 L2
extrude "Extrude9" add sketch "Sketch9" against normal up to surface (5 mm away) contours A0 L0 L1
fillet "Fillet1" radius 1 1 edges at (34.5, 0, -28.2317)
pattern_circular "C-Pattern2" count 20 over 360 about axis through (1.75, 0, 0) along (1, 0, 0) of "Extrude9", "Fillet1"
sketch "Sketch10" plane through (37, 0, 0) normal (1, 0, 0) x (0, 1, 0)
  arc A0 (-9.0842, -25.1558) -> (-7.4369, -25.691) centre (-8.1061, -24.9479) ccw
  line L0 (-7.4369, -25.691) -> (-3.5754, -22.2141)
  arc A1 (-3.5754, -22.2141) -> (-3.4641, -22.2317) centre (0, 0) ccw
  line L1 (-3.4641, -22.2317) -> (-0.866, -26.7317)
  arc A2 (-0.866, -26.7317) -> (0.866, -26.7317) centre (0, -26.2317) ccw
  line L2 (0.866, -26.7317) -> (3.4641, -22.2317)
  arc A3 (3.4641, -22.2317) -> (3.5754, -22.2141) centre (0, 0) ccw
  line L3 (3.5754, -22.2141) -> (7.4369, -25.691)
  arc A4 (7.4369, -25.691) -> (9.0842, -25.1558) centre (8.1061, -24.9479) ccw
  line L4 (9.0842, -25.1558) -> (10.1645, -20.0732)
  arc A5 (10.1645, -20.0732) -> (10.265, -20.022) centre (0, 0) ccw
  line L5 (10.265, -20.022) -> (15.0119, -22.1355)
  arc A6 (15.0119, -22.1355) -> (16.4131, -21.1174) centre (15.4186, -21.2219) ccw
  line L6 (16.4131, -21.1174) -> (15.87, -15.9497)
  arc A7 (15.87, -15.9497) -> (15.9497, -15.87) centre (0, 0) ccw
  line L7 (15.9497, -15.87) -> (21.1174, -16.4131)
  arc A8 (21.1174, -16.4131) -> (22.1355, -15.0119) centre (21.2219, -15.4186) ccw
  line L8 (22.1355, -15.0119) -> (20.022, -10.265)
  arc A9 (20.022, -10.265) -> (20.0732, -10.1645) centre (0, 0) ccw
  line L9 (20.0732, -10.1645) -> (25.1558, -9.0842)
  arc A10 (25.1558, -9.0842) -> (25.691, -7.4369) centre (24.9479, -8.1061) ccw
  line L10 (25.691, -7.4369) -> (22.2141, -3.5754)
  arc A11 (22.2141, -3.5754) -> (22.2317, -3.4641) centre (0, 0) ccw
  line L11 (22.2317, -3.4641) -> (26.7317, -0.866)
  arc A12 (26.7317, -0.866) -> (26.7317, 0.866) centre (26.2317, 0) ccw
  line L12 (26.7317, 0.866) -> (22.2317, 3.4641)
  arc A13 (22.2317, 3.4641) -> (22.2141, 3.5754) centre (0, 0) ccw
  line L13 (22.2141, 3.5754) -> (25.691, 7.4369)
  arc A14 (25.691, 7.4369) -> (25.1558, 9.0842) centre (24.9479, 8.1061) ccw
  line L14 (25.1558, 9.0842) -> (20.0732, 10.1645)
  arc A15 (20.0732, 10.1645) -> (20.022, 10.265) centre (0, 0) ccw
  line L15 (20.022, 10.265) -> (22.1355, 15.0119)
  arc A16 (22.1355, 15.0119) -> (21.1174, 16.4131) centre (21.2219, 15.4186) ccw
  line L16 (21.1174, 16.4131) -> (15.9497, 15.87)
  arc A17 (15.9497, 15.87) -> (15.87, 15.9497) centre (0, 0) ccw
  line L17 (15.87, 15.9497) -> (16.4131, 21.1174)
  arc A18 (16.4131, 21.1174) -> (15.0119, 22.1355) centre (15.4186, 21.2219) ccw
  line L18 (15.0119, 22.1355) -> (10.265, 20.022)
  arc A19 (10.265, 20.022) -> (10.1645, 20.0732) centre (0, 0) ccw
  line L19 (10.1645, 20.0732) -> (9.0842, 25.1558)
  arc A20 (9.0842, 25.1558) -> (7.4369, 25.691) centre (8.1061, 24.9479) ccw
  line L20 (7.4369, 25.691) -> (3.5754, 22.2141)
  arc A21 (3.5754, 22.2141) -> (3.4641, 22.2317) centre (0, 0) ccw
  line L21 (3.4641, 22.2317) -> (0.866, 26.7317)
  arc A22 (0.866, 26.7317) -> (-0.866, 26.7317) centre (0, 26.2317) ccw
  line L22 (-0.866, 26.7317) -> (-3.4641, 22.2317)
  arc A23 (-3.4641, 22.2317) -> (-3.5754, 22.2141) centre (0, 0) ccw
  line L23 (-3.5754, 22.2141) -> (-7.4369, 25.691)
  arc A24 (-7.4369, 25.691) -> (-9.0842, 25.1558) centre (-8.1061, 24.9479) ccw
  line L24 (-9.0842, 25.1558) -> (-10.1645, 20.0732)
  arc A25 (-10.1645, 20.0732) -> (-10.265, 20.022) centre (0, 0) ccw
  line L25 (-10.265, 20.022) -> (-15.0119, 22.1355)
  arc A26 (-15.0119, 22.1355) -> (-16.4131, 21.1174) centre (-15.4186, 21.2219) ccw
  line L26 (-16.4131, 21.1174) -> (-15.87, 15.9497)
  arc A27 (-15.87, 15.9497) -> (-15.9497, 15.87) centre (0, 0) ccw
  line L27 (-15.9497, 15.87) -> (-21.1174, 16.4131)
  arc A28 (-21.1174, 16.4131) -> (-22.1355, 15.0119) centre (-21.2219, 15.4186) ccw
  line L28 (-22.1355, 15.0119) -> (-20.022, 10.265)
  arc A29 (-20.022, 10.265) -> (-20.0732, 10.1645) centre (0, 0) ccw
  line L29 (-20.0732, 10.1645) -> (-25.1558, 9.0842)
  arc A30 (-25.1558, 9.0842) -> (-25.691, 7.4369) centre (-24.9479, 8.1061) ccw
  line L30 (-25.691, 7.4369) -> (-22.2141, 3.5754)
  arc A31 (-22.2141, 3.5754) -> (-22.2317, 3.4641) centre (0, 0) ccw
  line L31 (-22.2317, 3.4641) -> (-26.7317, 0.866)
  arc A32 (-26.7317, 0.866) -> (-26.7317, -0.866) centre (-26.2317, 0) ccw
  line L32 (-26.7317, -0.866) -> (-22.2317, -3.4641)
  arc A33 (-22.2317, -3.4641) -> (-22.2141, -3.5754) centre (0, 0) ccw
  line L33 (-22.2141, -3.5754) -> (-25.691, -7.4369)
  arc A34 (-25.691, -7.4369) -> (-25.1558, -9.0842) centre (-24.9479, -8.1061) ccw
  line L34 (-25.1558, -9.0842) -> (-20.0732, -10.1645)
  arc A35 (-20.0732, -10.1645) -> (-20.022, -10.265) centre (0, 0) ccw
  line L35 (-20.022, -10.265) -> (-22.1355, -15.0119)
  arc A36 (-22.1355, -15.0119) -> (-21.1174, -16.4131) centre (-21.2219, -15.4186) ccw
  line L36 (-21.1174, -16.4131) -> (-15.9497, -15.87)
  arc A37 (-15.9497, -15.87) -> (-15.87, -15.9497) centre (0, 0) ccw
  line L37 (-15.87, -15.9497) -> (-16.4131, -21.1174)
  arc A38 (-16.4131, -21.1174) -> (-15.0119, -22.1355) centre (-15.4186, -21.2219) ccw
  line L38 (-15.0119, -22.1355) -> (-10.265, -20.022)
  arc A39 (-10.265, -20.022) -> (-10.1645, -20.0732) centre (0, 0) ccw
  line L39 (-10.1645, -20.0732) -> (-9.0842, -25.1558)
  circle A40 centre (0, 0) radius 5
  circle A41 centre (0, 0) radius 17.5
  arc A42 (16.9354, 4.4092) -> (-4.8387, -1.2598) centre (6.0484, 1.5747) ccw
  arc A43 (2.1966, 17.3616) -> (-9.6774, -2.5195) centre (6.0484, 1.5747) ccw
  arc A44 (-4.4092, 16.9354) -> (1.2598, -4.8387) centre (-1.5747, 6.0484) ccw
  arc A45 (-17.3616, 2.1966) -> (2.5195, -9.6774) centre (-1.5747, 6.0484) ccw
  arc A46 (-16.9354, -4.4092) -> (4.8387, 1.2598) centre (-6.0484, -1.5747) ccw
  arc A47 (-2.1966, -17.3616) -> (9.6774, 2.5195) centre (-6.0484, -1.5747) ccw
  arc A48 (4.4092, -16.9354) -> (-1.2598, 4.8387) centre (1.5747, -6.0484) ccw
  arc A49 (17.3616, -2.1966) -> (-2.5195, 9.6774) centre (1.5747, -6.0484) ccw
  dimension "d38" = 35
  dimension "d39" = 10
  dimension "d42" = 360
  constraint concentric A1 A40
  constraint concentric A40 A41
  constraint tangent A41 A42
  constraint tangent A40 A42
  constraint coincident A40 A42.end
  constraint coincident A41 A42.start
  constraint concentric A42 A43
  constraint coincident A41 A43.start
  measures "d38" diameter of A41
  measures "d39" diameter of A40
extrude "Extrude10" cut sketch "Sketch10" against normal blind 8 contours A41 A45 A46 | A41 A43 A44 | A41 A47 A48 | A41 A42 A49
